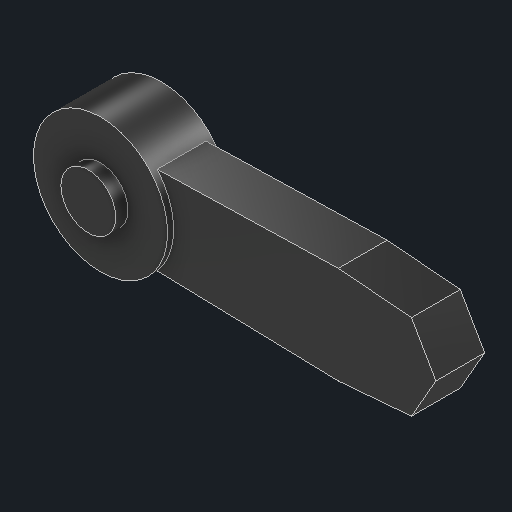
# Autodesk Inventor part: ra_lock_lever
Saved by Autodesk Inventor 2027.1 (Build 311270010, 270A)
## iProperties
Created: 2026-11-04
Part Number: ra_lock_lever
Material: Generic
Description: RA clutch lever
Document SubType Name: Modeling
Designer: Claude (from photos)
Density: 1 g/cm^3
Appearance: Glossy - Black
Author: alexg
Autodesk Inventor part; units mm, degrees
ref_plane "YZ Plane" through (0, 0, 0) normal (1, 0, 0) x (0, 1, 0)
sketch "Boss sketch" plane through (0, 0, 0) normal (0, 0, 1) x (1, 0, 0)
  circle A0 centre (0, 0) radius 11
  constraints: 1 centre point
extrude "Boss" add sketch "Boss sketch" along normal blind 10
ref_plane "Work Plane1" through (0, 0, 1) normal (0, 0, 1) x (1, 0, 0)
sketch "Lever arm sketch" plane through (0, 0, 1) normal (0, 0, 1) x (1, 0, 0)
  line L0 (0, -7) -> (38, -8)
  line L1 (38, -8) -> (50, -7)
  line L2 (50, -7) -> (54, 0)
  line L3 (54, 0) -> (50, 7)
  line L4 (50, 7) -> (38, 8)
  line L5 (38, 8) -> (0, 7)
  line L6 (0, 7) -> (0, -7)
  constraints: 14 end point
extrude "Lever arm" add sketch "Lever arm sketch" along normal blind 8
ref_plane "Work Plane2" through (0, 0, 10) normal (0, 0, 1) x (1, 0, 0)
sketch "Screw head sketch" plane through (0, 0, 10) normal (0, 0, 1) x (1, 0, 0)
  circle A0 centre (0, 0) radius 4.5
  constraints: 1 centre point
extrude "Screw head" add sketch "Screw head sketch" along normal blind 2
body "Solid1"
